gear-wheel (Autodesk Fusion 360 design; units mm, degrees)
description: Spur Gear; Module: 7.000000; Number of Teeth: 20; Pressure Angle: 20.000000; Root Fillet Radius: 0.040000; Clearance: 0.000000; Gear Thickness: 0.450000; Hole Diameter: 1.100000;
description: Spur Gear; Module: 7.000001; Number of Teeth: 20; Pressure Angle: 20.000009; Root Fillet Radius: 0.040000; Clearance: 0.000000; Gear Thickness: 0.450000; Hole Diameter: 0.410000;
Autodesk Fusion 360 part; units mm, degrees
(part 1 of 3)
sketch "스케치1" plane through (0, 2, 0) normal (0, -1, 0) x (1, 0, 0)
  circle A0 centre (48.541, -35.2671) radius 2.1
  circle A1 centre (48.541, 35.2671) radius 2.1
  circle A2 centre (-18.541, 57.0634) radius 2.1
  circle A3 centre (-60, 0) radius 2.1
  circle A4 centre (-18.541, -57.0634) radius 2.1
  circle A5 centre (-35.2671, -48.541) radius 2.1
  circle A6 centre (-57.0634, 18.541) radius 2.1
  circle A7 centre (0, 60) radius 2.1
  circle A8 centre (57.0634, 18.541) radius 2.1
  circle A9 centre (35.2671, -48.541) radius 2.1
  circle A10 centre (57.0634, -18.541) radius 2.1
  circle A11 centre (35.2671, 48.541) radius 2.1
  circle A12 centre (-35.2671, 48.541) radius 2.1
  circle A13 centre (-57.0634, -18.541) radius 2.1
  circle A14 centre (0, -60) radius 2.1
  circle A15 centre (-48.541, -35.2671) radius 2.1
  circle A16 centre (-48.541, 35.2671) radius 2.1
  circle A17 centre (18.541, 57.0634) radius 2.1
  circle A18 centre (60, 0) radius 2.1
  circle A19 centre (18.541, -57.0634) radius 2.1
  circle A20 centre (0, 0) radius 55
  line L0 (65.6169, 6.1447) -> (61.3802, 5.748)
  arc A21 (60.9449, 6.1063) -> (61.3802, 5.748) centre (61.3429, 6.1462) ccw
  arc A22 (60.9449, 6.1063) -> (59.849, 13.0255) centre (0, 0) ccw
  arc A23 (60.1522, 13.5009) -> (59.849, 13.0255) centre (60.2398, 13.1106) ccw
  line L1 (60.1522, 13.5009) -> (64.3042, 14.4328)
  spline S0 degree 3 poles (67.037, 15.6993) (66.4596, 15.3623) (65.8449, 15.0397) (64.8034, 14.5915) (64.4889, 14.4863) (64.3042, 14.4328) knots -0.138201 -0.138201 -0.138201 -0.138201 -0.057674 -0.057674 0 0 0 0
  spline S1 degree 3 poles (73.9529, 21.4743) (72.7669, 20.1834) (71.4866, 18.9537) (69.1517, 17.0681) (68.1109, 16.3282) (67.037, 15.6993) knots -0.894817 -0.894817 -0.894817 -0.894817 -0.373364 -0.373364 0 0 0 0
  arc A24 (73.9529, 21.4743) -> (72.4514, 26.0954) centre (0, 0) ccw
  spline S2 degree 3 poles (63.4618, 26.7024) (64.7004, 26.8248) (65.9772, 26.838) (68.9746, 26.6849) (70.7332, 26.4427) (72.4514, 26.0954) knots -0.90246 -0.90246 -0.90246 -0.90246 -0.525908 -0.525908 0 0 0 0
  spline S3 degree 3 poles (60.5066, 26.1207) (60.6874, 26.1859) (61.0038, 26.2857) (62.1098, 26.5353) (62.7967, 26.6356) (63.4618, 26.7024) knots -0.344173 -0.344173 -0.344173 -0.344173 -0.200542 -0.200542 0 0 0 0
  line L2 (60.5066, 26.1207) -> (56.5998, 24.4341)
  arc A25 (56.075, 24.6405) -> (56.5998, 24.4341) centre (56.4412, 24.8014) ccw
  arc A26 (56.075, 24.6405) -> (52.8946, 30.8824) centre (0, 0) ccw
  arc A27 (53.0362, 31.4282) -> (52.8946, 30.8824) centre (53.2401, 31.084) ccw
  line L3 (53.0362, 31.4282) -> (56.697, 33.5975)
  spline S4 degree 3 poles (58.9046, 35.6464) (58.4597, 35.1476) (57.9747, 34.6508) (57.1227, 33.9027) (56.856, 33.7055) (56.697, 33.5975) knots -0.138201 -0.138201 -0.138201 -0.138201 -0.057674 -0.057674 0 0 0 0
  spline S5 degree 3 poles (63.6975, 43.276) (62.9685, 41.6817) (62.1308, 40.1167) (60.4928, 37.6017) (59.7317, 36.5764) (58.9046, 35.6464) knots -0.894817 -0.894817 -0.894817 -0.894817 -0.373364 -0.373364 0 0 0 0
  arc A28 (63.6975, 43.276) -> (60.8415, 47.2069) centre (0, 0) ccw
  spline S6 degree 3 poles (52.1043, 45.0063) (53.2444, 45.5054) (54.4547, 45.9125) (57.3527, 46.6932) (59.1, 47.0062) (60.8415, 47.2069) knots -0.90246 -0.90246 -0.90246 -0.90246 -0.525908 -0.525908 0 0 0 0
  spline S7 degree 3 poles (49.4734, 43.5398) (49.6253, 43.6578) (49.8953, 43.8504) (50.87, 44.4295) (51.4924, 44.7373) (52.1043, 45.0063) knots -0.344173 -0.344173 -0.344173 -0.344173 -0.200542 -0.200542 0 0 0 0
  line L4 (49.4734, 43.5398) -> (46.279, 40.7285)
  arc A29 (45.7162, 40.7626) -> (46.279, 40.7285) centre (46.0148, 41.0288) ccw
  arc A30 (45.7162, 40.7626) -> (40.7626, 45.7162) centre (0, 0) ccw
  arc A31 (40.7285, 46.279) -> (40.7626, 45.7162) centre (41.0288, 46.0148) ccw
  line L5 (40.7285, 46.279) -> (43.5398, 49.4734)
  spline S8 degree 3 poles (45.0063, 52.1043) (44.7373, 51.4924) (44.4295, 50.87) (43.8504, 49.8953) (43.6578, 49.6253) (43.5398, 49.4734) knots -0.138201 -0.138201 -0.138201 -0.138201 -0.057674 -0.057674 0 0 0 0
  spline S9 degree 3 poles (47.2069, 60.8415) (47.0062, 59.1) (46.6932, 57.3527) (45.9125, 54.4547) (45.5054, 53.2444) (45.0063, 52.1043) knots -0.894817 -0.894817 -0.894817 -0.894817 -0.373364 -0.373364 0 0 0 0
  arc A32 (47.2069, 60.8415) -> (43.276, 63.6975) centre (0, 0) ccw
  spline S10 degree 3 poles (35.6464, 58.9046) (36.5764, 59.7317) (37.6017, 60.4928) (40.1167, 62.1308) (41.6817, 62.9685) (43.276, 63.6975) knots -0.90246 -0.90246 -0.90246 -0.90246 -0.525908 -0.525908 0 0 0 0
  spline S11 degree 3 poles (33.5975, 56.697) (33.7055, 56.856) (33.9027, 57.1227) (34.6508, 57.9747) (35.1476, 58.4597) (35.6464, 58.9046) knots -0.344173 -0.344173 -0.344173 -0.344173 -0.200542 -0.200542 0 0 0 0
  line L6 (33.5975, 56.697) -> (31.4282, 53.0362)
  arc A33 (30.8824, 52.8946) -> (31.4282, 53.0362) centre (31.084, 53.2401) ccw
  arc A34 (30.8824, 52.8946) -> (24.6405, 56.075) centre (0, 0) ccw
  arc A35 (24.4341, 56.5998) -> (24.6405, 56.075) centre (24.8014, 56.4412) ccw
  line L7 (24.4341, 56.5998) -> (26.1207, 60.5066)
  spline S12 degree 3 poles (26.7024, 63.4618) (26.6356, 62.7967) (26.5353, 62.1098) (26.2857, 61.0038) (26.1859, 60.6874) (26.1207, 60.5066) knots -0.138201 -0.138201 -0.138201 -0.138201 -0.057674 -0.057674 0 0 0 0
  spline S13 degree 3 poles (26.0954, 72.4514) (26.4427, 70.7332) (26.6849, 68.9746) (26.838, 65.9772) (26.8248, 64.7004) (26.7024, 63.4618) knots -0.894817 -0.894817 -0.894817 -0.894817 -0.373364 -0.373364 0 0 0 0
  arc A36 (26.0954, 72.4514) -> (21.4743, 73.9529) centre (0, 0) ccw
  spline S14 degree 3 poles (15.6993, 67.037) (16.3282, 68.1109) (17.0681, 69.1517) (18.9537, 71.4866) (20.1834, 72.7669) (21.4743, 73.9529) knots -0.90246 -0.90246 -0.90246 -0.90246 -0.525908 -0.525908 0 0 0 0
  spline S15 degree 3 poles (14.4328, 64.3042) (14.4863, 64.4889) (14.5915, 64.8034) (15.0397, 65.8449) (15.3623, 66.4596) (15.6993, 67.037) knots -0.344173 -0.344173 -0.344173 -0.344173 -0.200542 -0.200542 0 0 0 0
  line L8 (14.4328, 64.3042) -> (13.5009, 60.1522)
  arc A37 (13.0255, 59.849) -> (13.5009, 60.1522) centre (13.1106, 60.2398) ccw
  arc A38 (13.0255, 59.849) -> (6.1063, 60.9449) centre (0, 0) ccw
  arc A39 (5.748, 61.3802) -> (6.1063, 60.9449) centre (6.1462, 61.3429) ccw
  line L9 (5.748, 61.3802) -> (6.1447, 65.6169)
  spline S16 degree 3 poles (5.7847, 68.6073) (5.9268, 67.9541) (6.0436, 67.2697) (6.148, 66.1408) (6.1509, 65.8091) (6.1447, 65.6169) knots -0.138201 -0.138201 -0.138201 -0.138201 -0.057674 -0.057674 0 0 0 0
  spline S17 degree 3 poles (2.4294, 76.9693) (3.2907, 75.4425) (4.0645, 73.8449) (5.1364, 71.0415) (5.5184, 69.823) (5.7847, 68.6073) knots -0.894817 -0.894817 -0.894817 -0.894817 -0.373364 -0.373364 0 0 0 0
  arc A40 (2.4294, 76.9693) -> (-2.4294, 76.9693) centre (0, 0) ccw
  spline S18 degree 3 poles (-5.7847, 68.6073) (-5.5184, 69.823) (-5.1364, 71.0415) (-4.0645, 73.8449) (-3.2907, 75.4425) (-2.4294, 76.9693) knots -0.90246 -0.90246 -0.90246 -0.90246 -0.525908 -0.525908 0 0 0 0
  spline S19 degree 3 poles (-6.1447, 65.6169) (-6.1509, 65.8091) (-6.148, 66.1408) (-6.0436, 67.2697) (-5.9268, 67.9541) (-5.7847, 68.6073) knots -0.344173 -0.344173 -0.344173 -0.344173 -0.200542 -0.200542 0 0 0 0
  line L10 (-6.1447, 65.6169) -> (-5.748, 61.3802)
  arc A41 (-6.1063, 60.9449) -> (-5.748, 61.3802) centre (-6.1462, 61.3429) ccw
  arc A42 (-6.1063, 60.9449) -> (-13.0255, 59.849) centre (0, 0) ccw
  arc A43 (-13.5009, 60.1522) -> (-13.0255, 59.849) centre (-13.1106, 60.2398) ccw
  line L11 (-13.5009, 60.1522) -> (-14.4328, 64.3042)
  spline S20 degree 3 poles (-15.6993, 67.037) (-15.3623, 66.4596) (-15.0397, 65.8449) (-14.5915, 64.8034) (-14.4863, 64.4889) (-14.4328, 64.3042) knots -0.138201 -0.138201 -0.138201 -0.138201 -0.057674 -0.057674 0 0 0 0
  spline S21 degree 3 poles (-21.4743, 73.9529) (-20.1834, 72.7669) (-18.9537, 71.4866) (-17.0681, 69.1517) (-16.3282, 68.1109) (-15.6993, 67.037) knots -0.894817 -0.894817 -0.894817 -0.894817 -0.373364 -0.373364 0 0 0 0
  arc A44 (-21.4743, 73.9529) -> (-26.0954, 72.4514) centre (0, 0) ccw
  spline S22 degree 3 poles (-26.7024, 63.4618) (-26.8248, 64.7004) (-26.838, 65.9772) (-26.6849, 68.9746) (-26.4427, 70.7332) (-26.0954, 72.4514) knots -0.90246 -0.90246 -0.90246 -0.90246 -0.525908 -0.525908 0 0 0 0
  spline S23 degree 3 poles (-26.1207, 60.5066) (-26.1859, 60.6874) (-26.2857, 61.0038) (-26.5353, 62.1098) (-26.6356, 62.7967) (-26.7024, 63.4618) knots -0.344173 -0.344173 -0.344173 -0.344173 -0.200542 -0.200542 0 0 0 0
  line L12 (-26.1207, 60.5066) -> (-24.4341, 56.5998)
  arc A45 (-24.6405, 56.075) -> (-24.4341, 56.5998) centre (-24.8014, 56.4412) ccw
  arc A46 (-24.6405, 56.075) -> (-30.8824, 52.8946) centre (0, 0) ccw
  arc A47 (-31.4282, 53.0362) -> (-30.8824, 52.8946) centre (-31.084, 53.2401) ccw
  line L13 (-31.4282, 53.0362) -> (-33.5975, 56.697)
  spline S24 degree 3 poles (-35.6464, 58.9046) (-35.1476, 58.4597) (-34.6508, 57.9747) (-33.9027, 57.1227) (-33.7055, 56.856) (-33.5975, 56.697) knots -0.138201 -0.138201 -0.138201 -0.138201 -0.057674 -0.057674 0 0 0 0
  spline S25 degree 3 poles (-43.276, 63.6975) (-41.6817, 62.9685) (-40.1167, 62.1308) (-37.6017, 60.4928) (-36.5764, 59.7317) (-35.6464, 58.9046) knots -0.894817 -0.894817 -0.894817 -0.894817 -0.373364 -0.373364 0 0 0 0
  arc A48 (-43.276, 63.6975) -> (-47.2069, 60.8415) centre (0, 0) ccw
  spline S26 degree 3 poles (-45.0063, 52.1043) (-45.5054, 53.2444) (-45.9125, 54.4547) (-46.6932, 57.3527) (-47.0062, 59.1) (-47.2069, 60.8415) knots -0.90246 -0.90246 -0.90246 -0.90246 -0.525908 -0.525908 0 0 0 0
  spline S27 degree 3 poles (-43.5398, 49.4734) (-43.6578, 49.6253) (-43.8504, 49.8953) (-44.4295, 50.87) (-44.7373, 51.4924) (-45.0063, 52.1043) knots -0.344173 -0.344173 -0.344173 -0.344173 -0.200542 -0.200542 0 0 0 0
  line L14 (-43.5398, 49.4734) -> (-40.7285, 46.279)
  arc A49 (-40.7626, 45.7162) -> (-40.7285, 46.279) centre (-41.0288, 46.0148) ccw
  arc A50 (-40.7626, 45.7162) -> (-45.7162, 40.7626) centre (0, 0) ccw
  arc A51 (-46.279, 40.7285) -> (-45.7162, 40.7626) centre (-46.0148, 41.0288) ccw
  line L15 (-46.279, 40.7285) -> (-49.4734, 43.5398)
  spline S28 degree 3 poles (-52.1043, 45.0063) (-51.4924, 44.7373) (-50.87, 44.4295) (-49.8953, 43.8504) (-49.6253, 43.6578) (-49.4734, 43.5398) knots -0.138201 -0.138201 -0.138201 -0.138201 -0.057674 -0.057674 0 0 0 0
  spline S29 degree 3 poles (-60.8415, 47.2069) (-59.1, 47.0062) (-57.3527, 46.6932) (-54.4547, 45.9125) (-53.2444, 45.5054) (-52.1043, 45.0063) knots -0.894817 -0.894817 -0.894817 -0.894817 -0.373364 -0.373364 0 0 0 0
  arc A52 (-60.8415, 47.2069) -> (-63.6975, 43.276) centre (0, 0) ccw
  spline S30 degree 3 poles (-58.9046, 35.6464) (-59.7317, 36.5764) (-60.4928, 37.6017) (-62.1308, 40.1167) (-62.9685, 41.6817) (-63.6975, 43.276) knots -0.90246 -0.90246 -0.90246 -0.90246 -0.525908 -0.525908 0 0 0 0
  spline S31 degree 3 poles (-56.697, 33.5975) (-56.856, 33.7055) (-57.1227, 33.9027) (-57.9747, 34.6508) (-58.4597, 35.1476) (-58.9046, 35.6464) knots -0.344173 -0.344173 -0.344173 -0.344173 -0.200542 -0.200542 0 0 0 0
  line L16 (-56.697, 33.5975) -> (-53.0362, 31.4282)
  arc A53 (-52.8946, 30.8824) -> (-53.0362, 31.4282) centre (-53.2401, 31.084) ccw
  arc A54 (-52.8946, 30.8824) -> (-56.075, 24.6405) centre (0, 0) ccw
  arc A55 (-56.5998, 24.4341) -> (-56.075, 24.6405) centre (-56.4412, 24.8014) ccw
  line L17 (-56.5998, 24.4341) -> (-60.5066, 26.1207)
  spline S32 degree 3 poles (-63.4618, 26.7024) (-62.7967, 26.6356) (-62.1098, 26.5353) (-61.0038, 26.2857) (-60.6874, 26.1859) (-60.5066, 26.1207) knots -0.138201 -0.138201 -0.138201 -0.138201 -0.057674 -0.057674 0 0 0 0
  spline S33 degree 3 poles (-72.4514, 26.0954) (-70.7332, 26.4427) (-68.9746, 26.6849) (-65.9772, 26.838) (-64.7004, 26.8248) (-63.4618, 26.7024) knots -0.894817 -0.894817 -0.894817 -0.894817 -0.373364 -0.373364 0 0 0 0
  arc A56 (-72.4514, 26.0954) -> (-73.9529, 21.4743) centre (0, 0) ccw
  spline S34 degree 3 poles (-67.037, 15.6993) (-68.1109, 16.3282) (-69.1517, 17.0681) (-71.4866, 18.9537) (-72.7669, 20.1834) (-73.9529, 21.4743) knots -0.90246 -0.90246 -0.90246 -0.90246 -0.525908 -0.525908 0 0 0 0
  spline S35 degree 3 poles (-64.3042, 14.4328) (-64.4889, 14.4863) (-64.8034, 14.5915) (-65.8449, 15.0397) (-66.4596, 15.3623) (-67.037, 15.6993) knots -0.344173 -0.344173 -0.344173 -0.344173 -0.200542 -0.200542 0 0 0 0
  line L18 (-64.3042, 14.4328) -> (-60.1522, 13.5009)
  arc A57 (-59.849, 13.0255) -> (-60.1522, 13.5009) centre (-60.2398, 13.1106) ccw
  arc A58 (-59.849, 13.0255) -> (-60.9449, 6.1063) centre (0, 0) ccw
  arc A59 (-61.3802, 5.748) -> (-60.9449, 6.1063) centre (-61.3429, 6.1462) ccw
  line L19 (-61.3802, 5.748) -> (-65.6169, 6.1447)
  spline S36 degree 3 poles (-68.6073, 5.7847) (-67.9541, 5.9268) (-67.2697, 6.0436) (-66.1408, 6.148) (-65.8091, 6.1509) (-65.6169, 6.1447) knots -0.138201 -0.138201 -0.138201 -0.138201 -0.057674 -0.057674 0 0 0 0
  spline S37 degree 3 poles (-76.9693, 2.4294) (-75.4425, 3.2907) (-73.8449, 4.0645) (-71.0415, 5.1364) (-69.823, 5.5184) (-68.6073, 5.7847) knots -0.894817 -0.894817 -0.894817 -0.894817 -0.373364 -0.373364 0 0 0 0
  arc A60 (-76.9693, 2.4294) -> (-76.9693, -2.4294) centre (0, 0) ccw
  spline S38 degree 3 poles (-68.6073, -5.7847) (-69.823, -5.5184) (-71.0415, -5.1364) (-73.8449, -4.0645) (-75.4425, -3.2907) (-76.9693, -2.4294) knots -0.90246 -0.90246 -0.90246 -0.90246 -0.525908 -0.525908 0 0 0 0
  spline S39 degree 3 poles (-65.6169, -6.1447) (-65.8091, -6.1509) (-66.1408, -6.148) (-67.2697, -6.0436) (-67.9541, -5.9268) (-68.6073, -5.7847) knots -0.344173 -0.344173 -0.344173 -0.344173 -0.200542 -0.200542 0 0 0 0
  line L20 (-65.6169, -6.1447) -> (-61.3802, -5.748)
  arc A61 (-60.9449, -6.1063) -> (-61.3802, -5.748) centre (-61.3429, -6.1462) ccw
  arc A62 (-60.9449, -6.1063) -> (-59.849, -13.0255) centre (0, 0) ccw
  arc A63 (-60.1522, -13.5009) -> (-59.849, -13.0255) centre (-60.2398, -13.1106) ccw
  line L21 (-60.1522, -13.5009) -> (-64.3042, -14.4328)
  spline S40 degree 3 poles (-67.037, -15.6993) (-66.4596, -15.3623) (-65.8449, -15.0397) (-64.8034, -14.5915) (-64.4889, -14.4863) (-64.3042, -14.4328) knots -0.138201 -0.138201 -0.138201 -0.138201 -0.057674 -0.057674 0 0 0 0
  spline S41 degree 3 poles (-73.9529, -21.4743) (-72.7669, -20.1834) (-71.4866, -18.9537) (-69.1517, -17.0681) (-68.1109, -16.3282) (-67.037, -15.6993) knots -0.894817 -0.894817 -0.894817 -0.894817 -0.373364 -0.373364 0 0 0 0
  arc A64 (-73.9529, -21.4743) -> (-72.4514, -26.0954) centre (0, 0) ccw
  spline S42 degree 3 poles (-63.4618, -26.7024) (-64.7004, -26.8248) (-65.9772, -26.838) (-68.9746, -26.6849) (-70.7332, -26.4427) (-72.4514, -26.0954) knots -0.90246 -0.90246 -0.90246 -0.90246 -0.525908 -0.525908 0 0 0 0
  spline S43 degree 3 poles (-60.5066, -26.1207) (-60.6874, -26.1859) (-61.0038, -26.2857) (-62.1098, -26.5353) (-62.7967, -26.6356) (-63.4618, -26.7024) knots -0.344173 -0.344173 -0.344173 -0.344173 -0.200542 -0.200542 0 0 0 0
  line L22 (-60.5066, -26.1207) -> (-56.5998, -24.4341)
  arc A65 (-56.075, -24.6405) -> (-56.5998, -24.4341) centre (-56.4412, -24.8014) ccw
  arc A66 (-56.075, -24.6405) -> (-52.8946, -30.8824) centre (0, 0) ccw
  arc A67 (-53.0362, -31.4282) -> (-52.8946, -30.8824) centre (-53.2401, -31.084) ccw
  line L23 (-53.0362, -31.4282) -> (-56.697, -33.5975)
  spline S44 degree 3 poles (-58.9046, -35.6464) (-58.4597, -35.1476) (-57.9747, -34.6508) (-57.1227, -33.9027) (-56.856, -33.7055) (-56.697, -33.5975) knots -0.138201 -0.138201 -0.138201 -0.138201 -0.057674 -0.057674 0 0 0 0
  spline S45 degree 3 poles (-63.6975, -43.276) (-62.9685, -41.6817) (-62.1308, -40.1167) (-60.4928, -37.6017) (-59.7317, -36.5764) (-58.9046, -35.6464) knots -0.894817 -0.894817 -0.894817 -0.894817 -0.373364 -0.373364 0 0 0 0
  arc A68 (-63.6975, -43.276) -> (-60.8415, -47.2069) centre (0, 0) ccw
  spline S46 degree 3 poles (-52.1043, -45.0063) (-53.2444, -45.5054) (-54.4547, -45.9125) (-57.3527, -46.6932) (-59.1, -47.0062) (-60.8415, -47.2069) knots -0.90246 -0.90246 -0.90246 -0.90246 -0.525908 -0.525908 0 0 0 0
  spline S47 degree 3 poles (-49.4734, -43.5398) (-49.6253, -43.6578) (-49.8953, -43.8504) (-50.87, -44.4295) (-51.4924, -44.7373) (-52.1043, -45.0063) knots -0.344173 -0.344173 -0.344173 -0.344173 -0.200542 -0.200542 0 0 0 0
  line L24 (-49.4734, -43.5398) -> (-46.279, -40.7285)
  arc A69 (-45.7162, -40.7626) -> (-46.279, -40.7285) centre (-46.0148, -41.0288) ccw
  arc A70 (-45.7162, -40.7626) -> (-40.7626, -45.7162) centre (0, 0) ccw
  arc A71 (-40.7285, -46.279) -> (-40.7626, -45.7162) centre (-41.0288, -46.0148) ccw
  line L25 (-40.7285, -46.279) -> (-43.5398, -49.4734)
  spline S48 degree 3 poles (-45.0063, -52.1043) (-44.7373, -51.4924) (-44.4295, -50.87) (-43.8504, -49.8953) (-43.6578, -49.6253) (-43.5398, -49.4734) knots -0.138201 -0.138201 -0.138201 -0.138201 -0.057674 -0.057674 0 0 0 0
  spline S49 degree 3 poles (-47.2069, -60.8415) (-47.0062, -59.1) (-46.6932, -57.3527) (-45.9125, -54.4547) (-45.5054, -53.2444) (-45.0063, -52.1043) knots -0.894817 -0.894817 -0.894817 -0.894817 -0.373364 -0.373364 0 0 0 0
  arc A72 (-47.2069, -60.8415) -> (-43.276, -63.6975) centre (0, 0) ccw
  spline S50 degree 3 poles (-35.6464, -58.9046) (-36.5764, -59.7317) (-37.6017, -60.4928) (-40.1167, -62.1308) (-41.6817, -62.9685) (-43.276, -63.6975) knots -0.90246 -0.90246 -0.90246 -0.90246 -0.525908 -0.525908 0 0 0 0
  spline S51 degree 3 poles (-33.5975, -56.697) (-33.7055, -56.856) (-33.9027, -57.1227) (-34.6508, -57.9747) (-35.1476, -58.4597) (-35.6464, -58.9046) knots -0.344173 -0.344173 -0.344173 -0.344173 -0.200542 -0.200542 0 0 0 0
  line L26 (-33.5975, -56.697) -> (-31.4282, -53.0362)
  arc A73 (-30.8824, -52.8946) -> (-31.4282, -53.0362) centre (-31.084, -53.2401) ccw
  arc A74 (-30.8824, -52.8946) -> (-24.6405, -56.075) centre (0, 0) ccw
  arc A75 (-24.4341, -56.5998) -> (-24.6405, -56.075) centre (-24.8014, -56.4412) ccw
  line L27 (-24.4341, -56.5998) -> (-26.1207, -60.5066)
  spline S52 degree 3 poles (-26.7024, -63.4618) (-26.6356, -62.7967) (-26.5353, -62.1098) (-26.2857, -61.0038) (-26.1859, -60.6874) (-26.1207, -60.5066) knots -0.138201 -0.138201 -0.138201 -0.138201 -0.057674 -0.057674 0 0 0 0
  spline S53 degree 3 poles (-26.0954, -72.4514) (-26.4427, -70.7332) (-26.6849, -68.9746) (-26.838, -65.9772) (-26.8248, -64.7004) (-26.7024, -63.4618) knots -0.894817 -0.894817 -0.894817 -0.894817 -0.373364 -0.373364 0 0 0 0
  arc A76 (-26.0954, -72.4514) -> (-21.4743, -73.9529) centre (0, 0) ccw
  spline S54 degree 3 poles (-15.6993, -67.037) (-16.3282, -68.1109) (-17.0681, -69.1517) (-18.9537, -71.4866) (-20.1834, -72.7669) (-21.4743, -73.9529) knots -0.90246 -0.90246 -0.90246 -0.90246 -0.525908 -0.525908 0 0 0 0
  spline S55 degree 3 poles (-14.4328, -64.3042) (-14.4863, -64.4889) (-14.5915, -64.8034) (-15.0397, -65.8449) (-15.3623, -66.4596) (-15.6993, -67.037) knots -0.344173 -0.344173 -0.344173 -0.344173 -0.200542 -0.200542 0 0 0 0
  line L28 (-14.4328, -64.3042) -> (-13.5009, -60.1522)
  arc A77 (-13.0255, -59.849) -> (-13.5009, -60.1522) centre (-13.1106, -60.2398) ccw
  arc A78 (-13.0255, -59.849) -> (-6.1063, -60.9449) centre (0, 0) ccw
  arc A79 (-5.748, -61.3802) -> (-6.1063, -60.9449) centre (-6.1462, -61.3429) ccw
  line L29 (-5.748, -61.3802) -> (-6.1447, -65.6169)
  spline S56 degree 3 poles (-5.7847, -68.6073) (-5.9268, -67.9541) (-6.0436, -67.2697) (-6.148, -66.1408) (-6.1509, -65.8091) (-6.1447, -65.6169) knots -0.138201 -0.138201 -0.138201 -0.138201 -0.057674 -0.057674 0 0 0 0
  spline S57 degree 3 poles (-2.4294, -76.9693) (-3.2907, -75.4425) (-4.0645, -73.8449) (-5.1364, -71.0415) (-5.5184, -69.823) (-5.7847, -68.6073) knots -0.894817 -0.894817 -0.894817 -0.894817 -0.373364 -0.373364 0 0 0 0
  arc A80 (-2.4294, -76.9693) -> (2.4294, -76.9693) centre (0, 0) ccw
  spline S58 degree 3 poles (5.7847, -68.6073) (5.5184, -69.823) (5.1364, -71.0415) (4.0645, -73.8449) (3.2907, -75.4425) (2.4294, -76.9693) knots -0.90246 -0.90246 -0.90246 -0.90246 -0.525908 -0.525908 0 0 0 0
  spline S59 degree 3 poles (6.1447, -65.6169) (6.1509, -65.8091) (6.148, -66.1408) (6.0436, -67.2697) (5.9268, -67.9541) (5.7847, -68.6073) knots -0.344173 -0.344173 -0.344173 -0.344173 -0.200542 -0.200542 0 0 0 0
  line L30 (6.1447, -65.6169) -> (5.748, -61.3802)
  arc A81 (6.1063, -60.9449) -> (5.748, -61.3802) centre (6.1462, -61.3429) ccw
  arc A82 (6.1063, -60.9449) -> (13.0255, -59.849) centre (0, 0) ccw
  arc A83 (13.5009, -60.1522) -> (13.0255, -59.849) centre (13.1106, -60.2398) ccw
  line L31 (13.5009, -60.1522) -> (14.4328, -64.3042)
  spline S60 degree 3 poles (15.6993, -67.037) (15.3623, -66.4596) (15.0397, -65.8449) (14.5915, -64.8034) (14.4863, -64.4889) (14.4328, -64.3042) knots -0.138201 -0.138201 -0.138201 -0.138201 -0.057674 -0.057674 0 0 0 0
  spline S61 degree 3 poles (21.4743, -73.9529) (20.1834, -72.7669) (18.9537, -71.4866) (17.0681, -69.1517) (16.3282, -68.1109) (15.6993, -67.037) knots -0.894817 -0.894817 -0.894817 -0.894817 -0.373364 -0.373364 0 0 0 0
  arc A84 (21.4743, -73.9529) -> (26.0954, -72.4514) centre (0, 0) ccw
  spline S62 degree 3 poles (26.7024, -63.4618) (26.8248, -64.7004) (26.838, -65.9772) (26.6849, -68.9746) (26.4427, -70.7332) (26.0954, -72.4514) knots -0.90246 -0.90246 -0.90246 -0.90246 -0.525908 -0.525908 0 0 0 0
  spline S63 degree 3 poles (26.1207, -60.5066) (26.1859, -60.6874) (26.2857, -61.0038) (26.5353, -62.1098) (26.6356, -62.7967) (26.7024, -63.4618) knots -0.344173 -0.344173 -0.344173 -0.344173 -0.200542 -0.200542 0 0 0 0
  line L32 (26.1207, -60.5066) -> (24.4341, -56.5998)
  arc A85 (24.6405, -56.075) -> (24.4341, -56.5998) centre (24.8014, -56.4412) ccw
  arc A86 (24.6405, -56.075) -> (30.8824, -52.8946) centre (0, 0) ccw
  arc A87 (31.4282, -53.0362) -> (30.8824, -52.8946) centre (31.084, -53.2401) ccw
  line L33 (31.4282, -53.0362) -> (33.5975, -56.697)
  spline S64 degree 3 poles (35.6464, -58.9046) (35.1476, -58.4597) (34.6508, -57.9747) (33.9027, -57.1227) (33.7055, -56.856) (33.5975, -56.697) knots -0.138201 -0.138201 -0.138201 -0.138201 -0.057674 -0.057674 0 0 0 0
  spline S65 degree 3 poles (43.276, -63.6975) (41.6817, -62.9685) (40.1167, -62.1308) (37.6017, -60.4928) (36.5764, -59.7317) (35.6464, -58.9046) knots -0.894817 -0.894817 -0.894817 -0.894817 -0.373364 -0.373364 0 0 0 0
  arc A88 (43.276, -63.6975) -> (47.2069, -60.8415) centre (0, 0) ccw
  spline S66 degree 3 poles (45.0063, -52.1043) (45.5054, -53.2444) (45.9125, -54.4547) (46.6932, -57.3527) (47.0062, -59.1) (47.2069, -60.8415) knots -0.90246 -0.90246 -0.90246 -0.90246 -0.525908 -0.525908 0 0 0 0
  spline S67 degree 3 poles (43.5398, -49.4734) (43.6578, -49.6253) (43.8504, -49.8953) (44.4295, -50.87) (44.7373, -51.4924) (45.0063, -52.1043) knots -0.344173 -0.344173 -0.344173 -0.344173 -0.200542 -0.200542 0 0 0 0
  line L34 (43.5398, -49.4734) -> (40.7285, -46.279)
  arc A89 (40.7626, -45.7162) -> (40.7285, -46.279) centre (41.0288, -46.0148) ccw
  arc A90 (40.7626, -45.7162) -> (45.7162, -40.7626) centre (0, 0) ccw
  arc A91 (46.279, -40.7285) -> (45.7162, -40.7626) centre (46.0148, -41.0288) ccw
  line L35 (46.279, -40.7285) -> (49.4734, -43.5398)
  spline S68 degree 3 poles (52.1043, -45.0063) (51.4924, -44.7373) (50.87, -44.4295) (49.8953, -43.8504) (49.6253, -43.6578) (49.4734, -43.5398) knots -0.138201 -0.138201 -0.138201 -0.138201 -0.057674 -0.057674 0 0 0 0
  spline S69 degree 3 poles (60.8415, -47.2069) (59.1, -47.0062) (57.3527, -46.6932) (54.4547, -45.9125) (53.2444, -45.5054) (52.1043, -45.0063) knots -0.894817 -0.894817 -0.894817 -0.894817 -0.373364 -0.373364 0 0 0 0
  arc A92 (60.8415, -47.2069) -> (63.6975, -43.276) centre (0, 0) ccw
  spline S70 degree 3 poles (58.9046, -35.6464) (59.7317, -36.5764) (60.4928, -37.6017) (62.1308, -40.1167) (62.9685, -41.6817) (63.6975, -43.276) knots -0.90246 -0.90246 -0.90246 -0.90246 -0.525908 -0.525908 0 0 0 0
  spline S71 degree 3 poles (56.697, -33.5975) (56.856, -33.7055) (57.1227, -33.9027) (57.9747, -34.6508) (58.4597, -35.1476) (58.9046, -35.6464) knots -0.344173 -0.344173 -0.344173 -0.344173 -0.200542 -0.200542 0 0 0 0
  line L36 (56.697, -33.5975) -> (53.0362, -31.4282)
  arc A93 (52.8946, -30.8824) -> (53.0362, -31.4282) centre (53.2401, -31.084) ccw
  arc A94 (52.8946, -30.8824) -> (56.075, -24.6405) centre (0, 0) ccw
  arc A95 (56.5998, -24.4341) -> (56.075, -24.6405) centre (56.4412, -24.8014) ccw
  line L37 (56.5998, -24.4341) -> (60.5066, -26.1207)
  spline S72 degree 3 poles (63.4618, -26.7024) (62.7967, -26.6356) (62.1098, -26.5353) (61.0038, -26.2857) (60.6874, -26.1859) (60.5066, -26.1207) knots -0.138201 -0.138201 -0.138201 -0.138201 -0.057674 -0.057674 0 0 0 0
  spline S73 degree 3 poles (72.4514, -26.0954) (70.7332, -26.4427) (68.9746, -26.6849) (65.9772, -26.838) (64.7004, -26.8248) (63.4618, -26.7024) knots -0.894817 -0.894817 -0.894817 -0.894817 -0.373364 -0.373364 0 0 0 0
  arc A96 (72.4514, -26.0954) -> (73.9529, -21.4743) centre (0, 0) ccw
  spline S74 degree 3 poles (67.037, -15.6993) (68.1109, -16.3282) (69.1517, -17.0681) (71.4866, -18.9537) (72.7669, -20.1834) (73.9529, -21.4743) knots -0.90246 -0.90246 -0.90246 -0.90246 -0.525908 -0.525908 0 0 0 0
  spline S75 degree 3 poles (64.3042, -14.4328) (64.4889, -14.4863) (64.8034, -14.5915) (65.8449, -15.0397) (66.4596, -15.3623) (67.037, -15.6993) knots -0.344173 -0.344173 -0.344173 -0.344173 -0.200542 -0.200542 0 0 0 0
  line L38 (64.3042, -14.4328) -> (60.1522, -13.5009)
  arc A97 (59.849, -13.0255) -> (60.1522, -13.5009) centre (60.2398, -13.1106) ccw
  arc A98 (59.849, -13.0255) -> (60.9449, -6.1063) centre (0, 0) ccw
  arc A99 (61.3802, -5.748) -> (60.9449, -6.1063) centre (61.3429, -6.1462) ccw
  line L39 (61.3802, -5.748) -> (65.6169, -6.1447)
  spline S76 degree 3 poles (68.6073, -5.7847) (67.9541, -5.9268) (67.2697, -6.0436) (66.1408, -6.148) (65.8091, -6.1509) (65.6169, -6.1447) knots -0.138201 -0.138201 -0.138201 -0.138201 -0.057674 -0.057674 0 0 0 0
  spline S77 degree 3 poles (76.9693, -2.4294) (75.4425, -3.2907) (73.8449, -4.0645) (71.0415, -5.1364) (69.823, -5.5184) (68.6073, -5.7847) knots -0.894817 -0.894817 -0.894817 -0.894817 -0.373364 -0.373364 0 0 0 0
  arc A100 (76.9693, -2.4294) -> (76.9693, 2.4294) centre (0, 0) ccw
  spline S78 degree 3 poles (68.6073, 5.7847) (69.823, 5.5184) (71.0415, 5.1364) (73.8449, 4.0645) (75.4425, 3.2907) (76.9693, 2.4294) knots -0.90246 -0.90246 -0.90246 -0.90246 -0.525908 -0.525908 0 0 0 0
  spline S79 degree 3 poles (65.6169, 6.1447) (65.8091, 6.1509) (66.1408, 6.148) (67.2697, 6.0436) (67.9541, 5.9268) (68.6073, 5.7847) knots -0.344173 -0.344173 -0.344173 -0.344173 -0.200542 -0.200542 0 0 0 0
  circle A101 centre (-18.541, 57.0634) radius 2.05
  circle A102 centre (-35.2671, 48.541) radius 2.05
  circle A103 centre (-48.541, 35.2671) radius 2.05
  circle A104 centre (-57.0634, 18.541) radius 2.05
  circle A105 centre (-60, 0) radius 2.05
  circle A106 centre (-57.0634, -18.541) radius 2.05
  circle A107 centre (-48.541, -35.2671) radius 2.05
  circle A108 centre (-35.2671, -48.541) radius 2.05
  circle A109 centre (-18.541, -57.0634) radius 2.05
  circle A110 centre (0, -60) radius 2.05
  circle A111 centre (18.541, -57.0634) radius 2.05
  circle A112 centre (35.2671, -48.541) radius 2.05
  circle A113 centre (48.541, -35.2671) radius 2.05
  circle A114 centre (57.0634, -18.541) radius 2.05
  circle A115 centre (60, 0) radius 2.05
  circle A116 centre (57.0634, 18.541) radius 2.05
  circle A117 centre (48.541, 35.2671) radius 2.05
  circle A118 centre (35.2671, 48.541) radius 2.05
  circle A119 centre (18.541, 57.0634) radius 2.05
  circle A120 centre (0, 60) radius 2.05
  dimension "d1" = 4.1
  dimension "d3" = 360
  constraint concentric A2 A101
  measures "d1" diameter of A101
sketch "스케치1 (2)" plane through (0, 0, 0) normal (0, 1, 0) x (1, 0, 0) in component "Spur Gear (20 teeth)"
  arc A0 (59.849, -13.0255) -> (60.9449, -6.1063) centre (0, 0) ccw
  arc A1 (61.3802, -5.748) -> (60.9449, -6.1063) centre (61.3429, -6.1462) ccw
  line L0 (61.3802, -5.748) -> (65.6169, -6.1447)
  spline S0 degree 3 poles (65.6169, -6.1447) (65.9476, -6.1553) (66.9428, -6.1467) (68.6073, -5.7847) knots 0 0 0 0 1 1 1 1
  spline S1 degree 3 poles (68.6073, -5.7847) (70.5896, -5.3505) (73.448, -4.4158) (76.9693, -2.4294) knots 0 0 0 0 1 1 1 1
  arc A2 (76.9693, -2.4294) -> (76.9693, 2.4294) centre (0, 0) ccw
  spline S2 degree 3 poles (76.9693, 2.4294) (73.448, 4.4158) (70.5896, 5.3505) (68.6073, 5.7847) knots 0 0 0 0 1 1 1 1
  spline S3 degree 3 poles (68.6073, 5.7847) (66.9428, 6.1467) (65.9476, 6.1553) (65.6169, 6.1447) knots 0 0 0 0 1 1 1 1
  line L1 (65.6169, 6.1447) -> (61.3802, 5.748)
  arc A3 (60.9449, 6.1063) -> (61.3802, 5.748) centre (61.3429, 6.1462) ccw
  arc A4 (60.9449, 6.1063) -> (59.849, 13.0255) centre (0, 0) ccw
  arc A5 (60.1522, 13.5009) -> (59.849, 13.0255) centre (60.2398, 13.1106) ccw
  line L2 (60.1522, 13.5009) -> (64.3042, 14.4328)
  spline S4 degree 3 poles (64.3042, 14.4328) (64.622, 14.5249) (65.5658, 14.8406) (67.037, 15.6993) knots 0 0 0 0 1 1 1 1
  spline S5 degree 3 poles (67.037, 15.6993) (68.7881, 16.7247) (71.2178, 18.497) (73.9529, 21.4743) knots 0 0 0 0 1 1 1 1
  arc A6 (73.9529, 21.4743) -> (72.4514, 26.0954) centre (0, 0) ccw
  spline S6 degree 3 poles (72.4514, 26.0954) (68.4887, 26.8963) (65.4813, 26.9021) (63.4618, 26.7024) knots 0 0 0 0 1 1 1 1
  spline S7 degree 3 poles (63.4618, 26.7024) (61.7669, 26.5323) (60.8178, 26.2329) (60.5066, 26.1207) knots 0 0 0 0 1 1 1 1
  line L3 (60.5066, 26.1207) -> (56.5998, 24.4341)
  arc A7 (56.075, 24.6405) -> (56.5998, 24.4341) centre (56.4412, 24.8014) ccw
  arc A8 (56.075, 24.6405) -> (52.8946, 30.8824) centre (0, 0) ccw
  arc A9 (53.0362, 31.4282) -> (52.8946, 30.8824) centre (53.2401, 31.084) ccw
  line L4 (53.0362, 31.4282) -> (56.697, 33.5975)
  spline S8 degree 3 poles (56.697, 33.5975) (56.9707, 33.7833) (57.7708, 34.3752) (58.9046, 35.6464) knots 0 0 0 0 1 1 1 1
  spline S9 degree 3 poles (58.9046, 35.6464) (60.2532, 37.1628) (62.0162, 39.5992) (63.6975, 43.276) knots 0 0 0 0 1 1 1 1
  arc A10 (63.6975, 43.276) -> (60.8415, 47.2069) centre (0, 0) ccw
  spline S10 degree 3 poles (60.8415, 47.2069) (56.8252, 46.7441) (53.9632, 45.8202) (52.1043, 45.0063) knots 0 0 0 0 1 1 1 1
  spline S11 degree 3 poles (52.1043, 45.0063) (50.5449, 44.3208) (49.7347, 43.7427) (49.4734, 43.5398) knots 0 0 0 0 1 1 1 1
  line L5 (49.4734, 43.5398) -> (46.279, 40.7285)
  arc A11 (45.7162, 40.7626) -> (46.279, 40.7285) centre (46.0148, 41.0288) ccw
  arc A12 (45.7162, 40.7626) -> (40.7626, 45.7162) centre (0, 0) ccw
  arc A13 (40.7285, 46.279) -> (40.7626, 45.7162) centre (41.0288, 46.0148) ccw
  line L6 (40.7285, 46.279) -> (43.5398, 49.4734)
  spline S12 degree 3 poles (43.5398, 49.4734) (43.7427, 49.7347) (44.3208, 50.5449) (45.0063, 52.1043) knots 0 0 0 0 1 1 1 1
  spline S13 degree 3 poles (45.0063, 52.1043) (45.8202, 53.9632) (46.7441, 56.8252) (47.2069, 60.8415) knots 0 0 0 0 1 1 1 1
  arc A14 (47.2069, 60.8415) -> (43.276, 63.6975) centre (0, 0) ccw
  spline S14 degree 3 poles (43.276, 63.6975) (39.5992, 62.0162) (37.1628, 60.2532) (35.6464, 58.9046) knots 0 0 0 0 1 1 1 1
  spline S15 degree 3 poles (35.6464, 58.9046) (34.3752, 57.7708) (33.7833, 56.9707) (33.5975, 56.697) knots 0 0 0 0 1 1 1 1
  line L7 (33.5975, 56.697) -> (31.4282, 53.0362)
  arc A15 (30.8824, 52.8946) -> (31.4282, 53.0362) centre (31.084, 53.2401) ccw
  arc A16 (30.8824, 52.8946) -> (24.6405, 56.075) centre (0, 0) ccw
  arc A17 (24.4341, 56.5998) -> (24.6405, 56.075) centre (24.8014, 56.4412) ccw
  line L8 (24.4341, 56.5998) -> (26.1207, 60.5066)
  spline S16 degree 3 poles (26.1207, 60.5066) (26.2329, 60.8178) (26.5323, 61.7669) (26.7024, 63.4618) knots 0 0 0 0 1 1 1 1
  spline S17 degree 3 poles (26.7024, 63.4618) (26.9021, 65.4813) (26.8963, 68.4887) (26.0954, 72.4514) knots 0 0 0 0 1 1 1 1
  arc A18 (26.0954, 72.4514) -> (21.4743, 73.9529) centre (0, 0) ccw
  spline S18 degree 3 poles (21.4743, 73.9529) (18.497, 71.2178) (16.7247, 68.7881) (15.6993, 67.037) knots 0 0 0 0 1 1 1 1
  spline S19 degree 3 poles (15.6993, 67.037) (14.8406, 65.5658) (14.5249, 64.622) (14.4328, 64.3042) knots 0 0 0 0 1 1 1 1
  line L9 (14.4328, 64.3042) -> (13.5009, 60.1522)
  arc A19 (13.0255, 59.849) -> (13.5009, 60.1522) centre (13.1106, 60.2398) ccw
  arc A20 (13.0255, 59.849) -> (6.1063, 60.9449) centre (0, 0) ccw
  arc A21 (5.748, 61.3802) -> (6.1063, 60.9449) centre (6.1462, 61.3429) ccw
  line L10 (5.748, 61.3802) -> (6.1447, 65.6169)
  spline S20 degree 3 poles (6.1447, 65.6169) (6.1553, 65.9476) (6.1467, 66.9428) (5.7847, 68.6073) knots 0 0 0 0 1 1 1 1
  spline S21 degree 3 poles (5.7847, 68.6073) (5.3505, 70.5896) (4.4158, 73.448) (2.4294, 76.9693) knots 0 0 0 0 1 1 1 1
  arc A22 (2.4294, 76.9693) -> (-2.4294, 76.9693) centre (0, 0) ccw
  spline S22 degree 3 poles (-2.4294, 76.9693) (-4.4158, 73.448) (-5.3505, 70.5896) (-5.7847, 68.6073) knots 0 0 0 0 1 1 1 1
  spline S23 degree 3 poles (-5.7847, 68.6073) (-6.1467, 66.9428) (-6.1553, 65.9476) (-6.1447, 65.6169) knots 0 0 0 0 1 1 1 1
  line L11 (-6.1447, 65.6169) -> (-5.748, 61.3802)
  arc A23 (-6.1063, 60.9449) -> (-5.748, 61.3802) centre (-6.1462, 61.3429) ccw
  arc A24 (-6.1063, 60.9449) -> (-13.0255, 59.849) centre (0, 0) ccw
  arc A25 (-13.5009, 60.1522) -> (-13.0255, 59.849) centre (-13.1106, 60.2398) ccw
  line L12 (-13.5009, 60.1522) -> (-14.4328, 64.3042)
  spline S24 degree 3 poles (-14.4328, 64.3042) (-14.5249, 64.622) (-14.8406, 65.5658) (-15.6993, 67.037) knots 0 0 0 0 1 1 1 1
  spline S25 degree 3 poles (-15.6993, 67.037) (-16.7247, 68.7881) (-18.497, 71.2178) (-21.4743, 73.9529) knots 0 0 0 0 1 1 1 1
  arc A26 (-21.4743, 73.9529) -> (-26.0954, 72.4514) centre (0, 0) ccw
  spline S26 degree 3 poles (-26.0954, 72.4514) (-26.8963, 68.4887) (-26.9021, 65.4813) (-26.7024, 63.4618) knots 0 0 0 0 1 1 1 1
  spline S27 degree 3 poles (-26.7024, 63.4618) (-26.5323, 61.7669) (-26.2329, 60.8178) (-26.1207, 60.5066) knots 0 0 0 0 1 1 1 1
  line L13 (-26.1207, 60.5066) -> (-24.4341, 56.5998)
  arc A27 (-24.6405, 56.075) -> (-24.4341, 56.5998) centre (-24.8014, 56.4412) ccw
  arc A28 (-24.6405, 56.075) -> (-30.8824, 52.8946) centre (0, 0) ccw
  arc A29 (-31.4282, 53.0362) -> (-30.8824, 52.8946) centre (-31.084, 53.2401) ccw
  line L14 (-31.4282, 53.0362) -> (-33.5975, 56.697)
  spline S28 degree 3 poles (-33.5975, 56.697) (-33.7833, 56.9707) (-34.3752, 57.7708) (-35.6464, 58.9046) knots 0 0 0 0 1 1 1 1
  spline S29 degree 3 poles (-35.6464, 58.9046) (-37.1628, 60.2532) (-39.5992, 62.0162) (-43.276, 63.6975) knots 0 0 0 0 1 1 1 1
  arc A30 (-43.276, 63.6975) -> (-47.2069, 60.8415) centre (0, 0) ccw
  spline S30 degree 3 poles (-47.2069, 60.8415) (-46.7441, 56.8252) (-45.8202, 53.9632) (-45.0063, 52.1043) knots 0 0 0 0 1 1 1 1
  spline S31 degree 3 poles (-45.0063, 52.1043) (-44.3208, 50.5449) (-43.7427, 49.7347) (-43.5398, 49.4734) knots 0 0 0 0 1 1 1 1
  line L15 (-43.5398, 49.4734) -> (-40.7285, 46.279)
  arc A31 (-40.7626, 45.7162) -> (-40.7285, 46.279) centre (-41.0288, 46.0148) ccw
  arc A32 (-40.7626, 45.7162) -> (-45.7162, 40.7626) centre (0, 0) ccw
  arc A33 (-46.279, 40.7285) -> (-45.7162, 40.7626) centre (-46.0148, 41.0288) ccw
  line L16 (-46.279, 40.7285) -> (-49.4734, 43.5398)
  spline S32 degree 3 poles (-49.4734, 43.5398) (-49.7347, 43.7427) (-50.5449, 44.3208) (-52.1043, 45.0063) knots 0 0 0 0 1 1 1 1
  spline S33 degree 3 poles (-52.1043, 45.0063) (-53.9632, 45.8202) (-56.8252, 46.7441) (-60.8415, 47.2069) knots 0 0 0 0 1 1 1 1
  arc A34 (-60.8415, 47.2069) -> (-63.6975, 43.276) centre (0, 0) ccw
  spline S34 degree 3 poles (-63.6975, 43.276) (-62.0162, 39.5992) (-60.2532, 37.1628) (-58.9046, 35.6464) knots 0 0 0 0 1 1 1 1
  spline S35 degree 3 poles (-58.9046, 35.6464) (-57.7708, 34.3752) (-56.9707, 33.7833) (-56.697, 33.5975) knots 0 0 0 0 1 1 1 1
  line L17 (-56.697, 33.5975) -> (-53.0362, 31.4282)
  arc A35 (-52.8946, 30.8824) -> (-53.0362, 31.4282) centre (-53.2401, 31.084) ccw
  arc A36 (-52.8946, 30.8824) -> (-56.075, 24.6405) centre (0, 0) ccw
  arc A37 (-56.5998, 24.4341) -> (-56.075, 24.6405) centre (-56.4412, 24.8014) ccw
  line L18 (-56.5998, 24.4341) -> (-60.5066, 26.1207)
  spline S36 degree 3 poles (-60.5066, 26.1207) (-60.8178, 26.2329) (-61.7669, 26.5323) (-63.4618, 26.7024) knots 0 0 0 0 1 1 1 1
  spline S37 degree 3 poles (-63.4618, 26.7024) (-65.4813, 26.9021) (-68.4887, 26.8963) (-72.4514, 26.0954) knots 0 0 0 0 1 1 1 1
  arc A38 (-72.4514, 26.0954) -> (-73.9529, 21.4743) centre (0, 0) ccw
  spline S38 degree 3 poles (-73.9529, 21.4743) (-71.2178, 18.497) (-68.7881, 16.7247) (-67.037, 15.6993) knots 0 0 0 0 1 1 1 1
  spline S39 degree 3 poles (-67.037, 15.6993) (-65.5658, 14.8406) (-64.622, 14.5249) (-64.3042, 14.4328) knots 0 0 0 0 1 1 1 1
  line L19 (-64.3042, 14.4328) -> (-60.1522, 13.5009)
  arc A39 (-59.849, 13.0255) -> (-60.1522, 13.5009) centre (-60.2398, 13.1106) ccw
  arc A40 (-59.849, 13.0255) -> (-60.9449, 6.1063) centre (0, 0) ccw
  arc A41 (-61.3802, 5.748) -> (-60.9449, 6.1063) centre (-61.3429, 6.1462) ccw
  line L20 (-61.3802, 5.748) -> (-65.6169, 6.1447)
  spline S40 degree 3 poles (-65.6169, 6.1447) (-65.9476, 6.1553) (-66.9428, 6.1467) (-68.6073, 5.7847) knots 0 0 0 0 1 1 1 1
  spline S41 degree 3 poles (-68.6073, 5.7847) (-70.5896, 5.3505) (-73.448, 4.4158) (-76.9693, 2.4294) knots 0 0 0 0 1 1 1 1
  arc A42 (-76.9693, 2.4294) -> (-76.9693, -2.4294) centre (0, 0) ccw
  spline S42 degree 3 poles (-76.9693, -2.4294) (-73.448, -4.4158) (-70.5896, -5.3505) (-68.6073, -5.7847) knots 0 0 0 0 1 1 1 1
  spline S43 degree 3 poles (-68.6073, -5.7847) (-66.9428, -6.1467) (-65.9476, -6.1553) (-65.6169, -6.1447) knots 0 0 0 0 1 1 1 1
  line L21 (-65.6169, -6.1447) -> (-61.3802, -5.748)
  arc A43 (-60.9449, -6.1063) -> (-61.3802, -5.748) centre (-61.3429, -6.1462) ccw
  arc A44 (-60.9449, -6.1063) -> (-59.849, -13.0255) centre (0, 0) ccw
  arc A45 (-60.1522, -13.5009) -> (-59.849, -13.0255) centre (-60.2398, -13.1106) ccw
  line L22 (-60.1522, -13.5009) -> (-64.3042, -14.4328)
  spline S44 degree 3 poles (-64.3042, -14.4328) (-64.622, -14.5249) (-65.5658, -14.8406) (-67.037, -15.6993) knots 0 0 0 0 1 1 1 1
  spline S45 degree 3 poles (-67.037, -15.6993) (-68.7881, -16.7247) (-71.2178, -18.497) (-73.9529, -21.4743) knots 0 0 0 0 1 1 1 1
  arc A46 (-73.9529, -21.4743) -> (-72.4514, -26.0954) centre (0, 0) ccw
  spline S46 degree 3 poles (-72.4514, -26.0954) (-68.4887, -26.8963) (-65.4813, -26.9021) (-63.4618, -26.7024) knots 0 0 0 0 1 1 1 1
  spline S47 degree 3 poles (-63.4618, -26.7024) (-61.7669, -26.5323) (-60.8178, -26.2329) (-60.5066, -26.1207) knots 0 0 0 0 1 1 1 1
  line L23 (-60.5066, -26.1207) -> (-56.5998, -24.4341)
  arc A47 (-56.075, -24.6405) -> (-56.5998, -24.4341) centre (-56.4412, -24.8014) ccw
  arc A48 (-56.075, -24.6405) -> (-52.8946, -30.8824) centre (0, 0) ccw
  arc A49 (-53.0362, -31.4282) -> (-52.8946, -30.8824) centre (-53.2401, -31.084) ccw
  line L24 (-53.0362, -31.4282) -> (-56.697, -33.5975)
  spline S48 degree 3 poles (-56.697, -33.5975) (-56.9707, -33.7833) (-57.7708, -34.3752) (-58.9046, -35.6464) knots 0 0 0 0 1 1 1 1
  spline S49 degree 3 poles (-58.9046, -35.6464) (-60.2532, -37.1628) (-62.0162, -39.5992) (-63.6975, -43.276) knots 0 0 0 0 1 1 1 1
  arc A50 (-63.6975, -43.276) -> (-60.8415, -47.2069) centre (0, 0) ccw
  spline S50 degree 3 poles (-60.8415, -47.2069) (-56.8252, -46.7441) (-53.9632, -45.8202) (-52.1043, -45.0063) knots 0 0 0 0 1 1 1 1
  spline S51 degree 3 poles (-52.1043, -45.0063) (-50.5449, -44.3208) (-49.7347, -43.7427) (-49.4734, -43.5398) knots 0 0 0 0 1 1 1 1
  line L25 (-49.4734, -43.5398) -> (-46.279, -40.7285)
  arc A51 (-45.7162, -40.7626) -> (-46.279, -40.7285) centre (-46.0148, -41.0288) ccw
  arc A52 (-45.7162, -40.7626) -> (-40.7626, -45.7162) centre (0, 0) ccw
  arc A53 (-40.7285, -46.279) -> (-40.7626, -45.7162) centre (-41.0288, -46.0148) ccw
  line L26 (-40.7285, -46.279) -> (-43.5398, -49.4734)
  spline S52 degree 3 poles (-43.5398, -49.4734) (-43.7427, -49.7347) (-44.3208, -50.5449) (-45.0063, -52.1043) knots 0 0 0 0 1 1 1 1
  spline S53 degree 3 poles (-45.0063, -52.1043) (-45.8202, -53.9632) (-46.7441, -56.8252) (-47.2069, -60.8415) knots 0 0 0 0 1 1 1 1
  arc A54 (-47.2069, -60.8415) -> (-43.276, -63.6975) centre (0, 0) ccw
  spline S54 degree 3 poles (-43.276, -63.6975) (-39.5992, -62.0162) (-37.1628, -60.2532) (-35.6464, -58.9046) knots 0 0 0 0 1 1 1 1
  spline S55 degree 3 poles (-35.6464, -58.9046) (-34.3752, -57.7708) (-33.7833, -56.9707) (-33.5975, -56.697) knots 0 0 0 0 1 1 1 1
  line L27 (-33.5975, -56.697) -> (-31.4282, -53.0362)
  arc A55 (-30.8824, -52.8946) -> (-31.4282, -53.0362) centre (-31.084, -53.2401) ccw
  arc A56 (-30.8824, -52.8946) -> (-24.6405, -56.075) centre (0, 0) ccw
  arc A57 (-24.4341, -56.5998) -> (-24.6405, -56.075) centre (-24.8014, -56.4412) ccw
  line L28 (-24.4341, -56.5998) -> (-26.1207, -60.5066)
  spline S56 degree 3 poles (-26.1207, -60.5066) (-26.2329, -60.8178) (-26.5323, -61.7669) (-26.7024, -63.4618) knots 0 0 0 0 1 1 1 1
  spline S57 degree 3 poles (-26.7024, -63.4618) (-26.9021, -65.4813) (-26.8963, -68.4887) (-26.0954, -72.4514) knots 0 0 0 0 1 1 1 1
  arc A58 (-26.0954, -72.4514) -> (-21.4743, -73.9529) centre (0, 0) ccw
  spline S58 degree 3 poles (-21.4743, -73.9529) (-18.497, -71.2178) (-16.7247, -68.7881) (-15.6993, -67.037) knots 0 0 0 0 1 1 1 1
  spline S59 degree 3 poles (-15.6993, -67.037) (-14.8406, -65.5658) (-14.5249, -64.622) (-14.4328, -64.3042) knots 0 0 0 0 1 1 1 1
  line L29 (-14.4328, -64.3042) -> (-13.5009, -60.1522)
  arc A59 (-13.0255, -59.849) -> (-13.5009, -60.1522) centre (-13.1106, -60.2398) ccw
  arc A60 (-13.0255, -59.849) -> (-6.1063, -60.9449) centre (0, 0) ccw
  arc A61 (-5.748, -61.3802) -> (-6.1063, -60.9449) centre (-6.1462, -61.3429) ccw
  line L30 (-5.748, -61.3802) -> (-6.1447, -65.6169)
  spline S60 degree 3 poles (-6.1447, -65.6169) (-6.1553, -65.9476) (-6.1467, -66.9428) (-5.7847, -68.6073) knots 0 0 0 0 1 1 1 1
  spline S61 degree 3 poles (-5.7847, -68.6073) (-5.3505, -70.5896) (-4.4158, -73.448) (-2.4294, -76.9693) knots 0 0 0 0 1 1 1 1
  arc A62 (-2.4294, -76.9693) -> (2.4294, -76.9693) centre (0, 0) ccw
  spline S62 degree 3 poles (2.4294, -76.9693) (4.4158, -73.448) (5.3505, -70.5896) (5.7847, -68.6073) knots 0 0 0 0 1 1 1 1
  spline S63 degree 3 poles (5.7847, -68.6073) (6.1467, -66.9428) (6.1553, -65.9476) (6.1447, -65.6169) knots 0 0 0 0 1 1 1 1
  line L31 (6.1447, -65.6169) -> (5.748, -61.3802)
  arc A63 (6.1063, -60.9449) -> (5.748, -61.3802) centre (6.1462, -61.3429) ccw
  arc A64 (6.1063, -60.9449) -> (13.0255, -59.849) centre (0, 0) ccw
  arc A65 (13.5009, -60.1522) -> (13.0255, -59.849) centre (13.1106, -60.2398) ccw
  line L32 (13.5009, -60.1522) -> (14.4328, -64.3042)
  spline S64 degree 3 poles (14.4328, -64.3042) (14.5249, -64.622) (14.8406, -65.5658) (15.6993, -67.037) knots 0 0 0 0 1 1 1 1
  spline S65 degree 3 poles (15.6993, -67.037) (16.7247, -68.7881) (18.497, -71.2178) (21.4743, -73.9529) knots 0 0 0 0 1 1 1 1
  arc A66 (21.4743, -73.9529) -> (26.0954, -72.4514) centre (0, 0) ccw
  spline S66 degree 3 poles (26.0954, -72.4514) (26.8963, -68.4887) (26.9021, -65.4813) (26.7024, -63.4618) knots 0 0 0 0 1 1 1 1
  spline S67 degree 3 poles (26.7024, -63.4618) (26.5323, -61.7669) (26.2329, -60.8178) (26.1207, -60.5066) knots 0 0 0 0 1 1 1 1
  line L33 (26.1207, -60.5066) -> (24.4341, -56.5998)
  arc A67 (24.6405, -56.075) -> (24.4341, -56.5998) centre (24.8014, -56.4412) ccw
  arc A68 (24.6405, -56.075) -> (30.8824, -52.8946) centre (0, 0) ccw
  arc A69 (31.4282, -53.0362) -> (30.8824, -52.8946) centre (31.084, -53.2401) ccw
  line L34 (31.4282, -53.0362) -> (33.5975, -56.697)
  spline S68 degree 3 poles (33.5975, -56.697) (33.7833, -56.9707) (34.3752, -57.7708) (35.6464, -58.9046) knots 0 0 0 0 1 1 1 1
  spline S69 degree 3 poles (35.6464, -58.9046) (37.1628, -60.2532) (39.5992, -62.0162) (43.276, -63.6975) knots 0 0 0 0 1 1 1 1
  arc A70 (43.276, -63.6975) -> (47.2069, -60.8415) centre (0, 0) ccw
  spline S70 degree 3 poles (47.2069, -60.8415) (46.7441, -56.8252) (45.8202, -53.9632) (45.0063, -52.1043) knots 0 0 0 0 1 1 1 1
  spline S71 degree 3 poles (45.0063, -52.1043) (44.3208, -50.5449) (43.7427, -49.7347) (43.5398, -49.4734) knots 0 0 0 0 1 1 1 1
  line L35 (43.5398, -49.4734) -> (40.7285, -46.279)
  arc A71 (40.7626, -45.7162) -> (40.7285, -46.279) centre (41.0288, -46.0148) ccw
  arc A72 (40.7626, -45.7162) -> (45.7162, -40.7626) centre (0, 0) ccw
  arc A73 (46.279, -40.7285) -> (45.7162, -40.7626) centre (46.0148, -41.0288) ccw
  line L36 (46.279, -40.7285) -> (49.4734, -43.5398)
  spline S72 degree 3 poles (49.4734, -43.5398) (49.7347, -43.7427) (50.5449, -44.3208) (52.1043, -45.0063) knots 0 0 0 0 1 1 1 1
  spline S73 degree 3 poles (52.1043, -45.0063) (53.9632, -45.8202) (56.8252, -46.7441) (60.8415, -47.2069) knots 0 0 0 0 1 1 1 1
  arc A74 (60.8415, -47.2069) -> (63.6975, -43.276) centre (0, 0) ccw
  spline S74 degree 3 poles (63.6975, -43.276) (62.0162, -39.5992) (60.2532, -37.1628) (58.9046, -35.6464) knots 0 0 0 0 1 1 1 1
  spline S75 degree 3 poles (58.9046, -35.6464) (57.7708, -34.3752) (56.9707, -33.7833) (56.697, -33.5975) knots 0 0 0 0 1 1 1 1
  line L37 (56.697, -33.5975) -> (53.0362, -31.4282)
  arc A75 (52.8946, -30.8824) -> (53.0362, -31.4282) centre (53.2401, -31.084) ccw
  arc A76 (52.8946, -30.8824) -> (56.075, -24.6405) centre (0, 0) ccw
  arc A77 (56.5998, -24.4341) -> (56.075, -24.6405) centre (56.4412, -24.8014) ccw
  line L38 (56.5998, -24.4341) -> (60.5066, -26.1207)
  spline S76 degree 3 poles (60.5066, -26.1207) (60.8178, -26.2329) (61.7669, -26.5323) (63.4618, -26.7024) knots 0 0 0 0 1 1 1 1
  spline S77 degree 3 poles (63.4618, -26.7024) (65.4813, -26.9021) (68.4887, -26.8963) (72.4514, -26.0954) knots 0 0 0 0 1 1 1 1
  arc A78 (72.4514, -26.0954) -> (73.9529, -21.4743) centre (0, 0) ccw
  spline S78 degree 3 poles (73.9529, -21.4743) (71.2178, -18.497) (68.7881, -16.7247) (67.037, -15.6993) knots 0 0 0 0 1 1 1 1
  spline S79 degree 3 poles (67.037, -15.6993) (65.5658, -14.8406) (64.622, -14.5249) (64.3042, -14.4328) knots 0 0 0 0 1 1 1 1
  line L39 (64.3042, -14.4328) -> (60.1522, -13.5009)
  arc A79 (59.849, -13.0255) -> (60.1522, -13.5009) centre (60.2398, -13.1106) ccw
  circle A80 centre (0, 0) radius 5.5
extrude "돌출1" add sketch "스케치1 (2)" along normal blind 4.5 makes body 1 in component "Spur Gear (20 teeth)"
sketch "스케치2" plane through (0, 0, 0) normal (0, 1, 0) x (1, 0, 0) in component "Spur Gear (20 teeth)"
  circle A0 centre (0, 0) radius 70 construction
sketch "스케치2 (2)" plane through (0, 0, 0) normal (0, 1, 0) x (1, 0, 0)
  circle A0 centre (0, 0) radius 55
  circle A1 centre (0, -60) radius 2.05
  circle A2 centre (60, 0) radius 2.05
  circle A3 centre (0, 60) radius 2.05
  circle A4 centre (-60, 0) radius 2.05
  dimension "d6" = 110
  dimension "d7" = 4.1
  dimension "d8" = 60
  dimension "d10" = 360
  constraint coincident A0.centre origin
  measures "d6" diameter of A0
  measures "d7" diameter of A1
  measures "d8" distance of A0.centre A1.centre
extrude "돌출2" cut sketch "스케치2 (2)" along normal blind 5 bodies 1 in component "Spur Gear (20 teeth)"